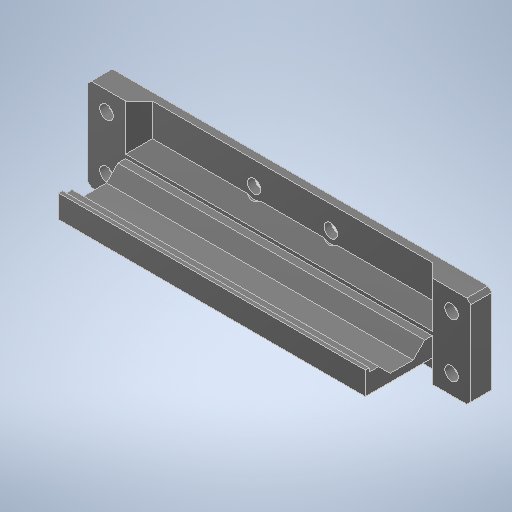
# Autodesk Inventor part: 3D_XT30-fix2
Saved by Autodesk Inventor 2025.3 (Build 293356030, 356C)
## iProperties
Created: 2025-09-07
Part Number: 3D_XT30-fix2
Material: 一般
Document SubType Name: Modeling
Designer: ibuki_ono
Density: 1 g/cm^3
Appearance: 滑らか - 黒
Author: ibuki_ono
## iProperties of the stored document 3D_XT30-fix2_3D プリント.ipt
Created: 2025-09-08
Part Number: 3D_XT30-fix2_3D プリント
Material: 一般
Document SubType Name: Modeling
Designer: ibuki_ono
Density: 1 g/cm^3
Appearance: 既定
Author: ibuki_ono
Autodesk Inventor part; units mm, degrees
(part 1 of 2)
ref_plane "YZ Plane" through (0, 0, 0) normal (1, 0, 0) x (0, 1, 0)
ref_plane "XZ Plane" through (0, 0, 0) normal (0, 1, 0) x (-1, 0, 0)
ref_plane "XY Plane" through (0, 0, 0) normal (0, 0, 1) x (1, 0, 0)
sketch "スケッチ1" plane through (0, 0, 0) normal (0, 0, 1) x (1, 0, 0)
  line L0 (-48, -5) -> (48, -5)
  line L1 (48, -5) -> (48, 5)
  line L2 (48, 5) -> (-48, 5)
  line L3 (-48, 5) -> (-48, -5)
  line L4 (-48, -5) -> (48, 5) construction
  line L5 (48, -5) -> (-48, 5) construction
  line L6 (-50, 7) -> (50, 7)
  line L7 (50, 7) -> (50, -7)
  line L8 (50, -7) -> (-50, -7)
  line L9 (-50, -7) -> (-50, 7)
  line L10 (-50, 5) -> (50, 5)
  line L11 (50, 5) -> (50, 17)
  line L12 (50, 17) -> (-50, 17)
  line L13 (-50, 17) -> (-50, 5)
  point P0 (0, 0)
  dimension "d0" = 96
  dimension "d1" = 10
  dimension "d2" = 2
  dimension "d3" = 12
  constraints: 28 end point, 6 parallel, 3 perpendicular, 2 horizontal, 2 midpoint, 1 collinear, 1 horizontal alignment, 1 point on line, 3 other
  measures "d0" distance of L2.end L1.end
  measures "d1" distance of L1.end L0.end
  measures "d2" distance between parallel lines of L2 L6
  measures "d3" distance of L12.end L10.start
extrude "押し出し1" add sketch "スケッチ1" along normal blind 2
sketch "スケッチ3" plane through (0, 0, 2) normal (0, 0, 1) x (1, 0, 0)
  line L0 (50, 17) -> (-50, 17) projected
  line L1 (50, -7) -> (50, 17) projected
  line L2 (-50, 17) -> (50, 17)
  line L3 (50, 17) -> (50, 5)
  line L4 (50, 5) -> (-50, 5)
  line L5 (-50, 5) -> (-50, 17)
  line L6 (-40, 5) -> (40, 5)
  line L7 (40, 5) -> (40, -1)
  line L8 (40, -1) -> (-40, -1)
  line L9 (-40, -1) -> (-40, 5)
  point P0 (0, 0)
  point P1 (0, 5)
  point P2 (40, 5)
  dimension "d6" = 12
  dimension "d7" = 80
  dimension "d8" = 6
  constraints: 16 end point, 4 parallel, 3 midpoint, 2 horizontal, 2 perpendicular, 1 point on line
  measures "d6" distance of L2.end L3.end
  measures "d7" distance of L7.end L8.end
  measures "d8" distance of L6.end L7.end
extrude "押し出し2" add sketch "スケッチ3" along normal blind 21 contours L7 L8 L9 L4
sketch "スケッチ5" plane through (-40, 5, 2) normal (0, 1, 0) x (1, 0, 0)
  line L0 (0, 0) -> (80, 0) projected
  line L1 (0, 0) -> (0, -21) projected
  line L2 (80, -21) -> (0, -21) projected
  line L3 (80, 0) -> (80, -21) projected
  line L4 (0, -20) -> (80, -20)
  line L5 (80, -20) -> (80, -3.5)
  line L6 (80, -3.5) -> (0, -3.5)
  line L7 (0, -3.5) -> (0, -20)
  point P0 (40, 2)
  point P1 (0, -3.5)
  dimension "d11" = 16.5
  dimension "d12" = 1
  constraints: 8 end point, 2 parallel, 2 point on line, 1 horizontal, 1 perpendicular
  measures "d11" distance between parallel lines of L6 L4
  measures "d12" distance between parallel lines of L2 L4
extrude "押し出し3" cut sketch "スケッチ5" against normal blind 1 contours L6 L3 L4 L1
sketch "スケッチ6" plane through (0, 0, 2) normal (0, 0, 1) x (1, 0, 0)
  line L0 (-50, 17) -> (-50, -7) projected
  line L1 (50, 17) -> (-50, 17) projected
  line L2 (-40, 5) -> (-40, -1) projected
  line L3 (-50, -7) -> (50, -7) projected
  line L4 (-50, -7) -> (-40, -7)
  line L5 (-40, -7) -> (-40, 17)
  line L6 (-40, 17) -> (-50, 17)
  line L7 (-50, 17) -> (-50, -7)
  point P0 (0, 0)
  point P1 (-40, -1)
  constraints: 8 end point, 2 parallel, 1 collinear, 1 horizontal, 1 perpendicular, 1 point on line
extrude "押し出し4" add sketch "スケッチ6" along normal blind 3.5
sketch "スケッチ7" plane through (-40, 4, 2) normal (0, 1, 0) x (1, 0, 0)
  line L0 (80, -3.5) -> (80, -20) projected
  line L1 (0, -3.5) -> (0, -21) projected
  line L2 (80, -17.5) -> (0, -17.5)
  line L3 (0, -17.5) -> (0, -5.5)
  line L4 (0, -5.5) -> (80, -5.5)
  line L5 (80, -5.5) -> (80, -17.5)
  line L6 (80, -20) -> (0, -20) projected
  point P0 (40, 2)
  point P1 (0, -17.5)
  dimension "d20" = 12
  dimension "d27" = 2.5
  constraints: 8 end point, 2 parallel, 2 point on line, 1 horizontal, 1 perpendicular
  measures "d20" distance between parallel lines of L2 L4
  measures "d27" distance between parallel lines of L6 L2
extrude "押し出し5" cut sketch "スケッチ7" against normal blind 3 contours L0 L2 L1 L4
chamfer "面取り2" distance 3 angle 45 2 edges at (0, 1, 7.5) (0, 1, 19.5)
sketch "スケッチ8" plane through (-40, 4, 5.5) normal (0, 0, 1) x (1, 0, 0)
  line L0 (0, 13) -> (-10, 13) projected
  line L1 (-10, -11) -> (0, -11) projected
  line L2 (-5, 13) -> (-5, -11) construction
  point P0 (40, -4)
  point P1 (-5, 8)
  point P2 (-5, -6)
  dimension "d28" = 5
  dimension "d29" = 5
  constraints: 2 end point, 2 midpoint, 2 point on line
  measures "d28" distance from line of L0 point (-5, 8)
  measures "d29" distance from line of L1 point (-5, -6)
hole "穴1" at (-45, 12, 5.5) at (-45, -2, 5.5) direction (0, 0, -1) diameter 3.5 end through all
sketch "スケッチ9" plane through (0, 0, 0) normal (0, 0, -1) x (-1, 0, 0)
  circle A0 centre (45, -2) radius 1.75 projected
  line L0 (45, -5.1754) -> (42.25, -3.5877)
  line L1 (42.25, -3.5877) -> (42.25, -0.4123)
  line L2 (42.25, -0.4123) -> (45, 1.1754)
  line L3 (45, 1.1754) -> (47.75, -0.4123)
  line L4 (47.75, -0.4123) -> (47.75, -3.5877)
  line L5 (47.75, -3.5877) -> (45, -5.1754)
  point P0 (0, 0)
  dimension "d37" = 5.5
  constraints: 12 end point, 1 coincident, 1 vertical alignment, 13 other
  measures "d37" distance between parallel lines of L1 L4
extrude "押し出し6" cut sketch "スケッチ9" against normal blind 3
sketch "スケッチ10" plane through (0, 0, 3) normal (0, 0, -1) x (-1, 0, 0)
  line L0 (47.75, -0.4123) -> (47.75, -3.5877) projected
  line L1 (45, 1.1754) -> (47.75, -0.4123) projected
  line L2 (42.25, -0.4123) -> (45, 1.1754) projected
  line L3 (42.25, -3.5877) -> (42.25, -0.4123) projected
  line L4 (45, -5.1754) -> (42.25, -3.5877) projected
  line L5 (47.75, -3.5877) -> (45, -5.1754) projected
  circle A0 centre (45, -2) radius 1.75 projected
  line L6 (46.75, -4.1651) -> (46.75, 0.1651)
  line L7 (46, 0.5981) -> (42.25, -1.567)
  line L8 (42.25, -2.433) -> (46, -4.5981)
  line L9 (45, -5.1754) -> (42.25, -3.5877) projected
  line L10 (47.75, -0.4123) -> (47.75, -3.5877) projected
  line L11 (42.25, -0.4123) -> (45, 1.1754) projected
  circle A1 centre (45, -2) radius 1.75 projected
  point P0 (0, 0)
  point P1 (44.125, -3.5155)
  point P2 (44.125, -0.4845)
  point P3 (46.75, -2)
  constraints: 6 end point, 6 point on line, 4 parallel, 3 tangent, 1 vertical
extrude "押し出し7" cut sketch "スケッチ10" against normal blind 0.2 contours L6 A0 L7 L1 | L5 L8 A0 L6 | A0 L8 L3 L7
pattern_linear "矩形状パターン1" count 2 spacing 14 along (0, 1, 0) of "押し出し6", "押し出し7"
mirror "ミラー1" about plane through (0, 0, 0) normal (1, 0, 0) of "押し出し4", "穴1", "押し出し6", "押し出し7", "矩形状パターン1"
chamfer "面取り3" distance 1 angle 45 4 edges at (-50, -7, 2.75) (-50, 17, 2.75) (50, -7, 2.75) (50, 17, 2.75)
chamfer "面取り4" distance 3.5 angle 45 8 edges at (-40, -4, 2) (-40, -1, 3.75) (0, -1, 2) (40, -4, 2) (40, -1, 3.75) (40, 11, 2) (0, 5, 2) (-40, 11, 2)
sketch "スケッチ11" plane through (0, 0, 2) normal (0, 0, 1) x (1, 0, 0)
  line L0 (-10, 11) -> (10, 11) construction
  line L1 (-10, 11) -> (10, 11) construction
  line L2 (36.5, 17) -> (-36.5, 17) construction
  point P0 (0, 0)
  point P1 (0, 11)
  point P2 (0, 17)
  dimension "d51" = 20
  dimension "d52" = 0
  dimension "d53" = 6
  constraints: 4 end point, 2 coincident, 2 horizontal, 2 midpoint, 1 collinear, 1 vertical alignment
  measures "d51" distance of L0.start L0.end
  measures "d52" distance between parallel lines of L0 L1
  measures "d53" distance between parallel lines of L2 L0
hole "穴2" at (-10, 11, 2) at (10, 11, 2) direction (0, 0, -1) diameter 3.5 end through all
sketch "スケッチ12" plane through (0, 0, 2) normal (0, 0, 1) x (1, 0, 0)
  circle A0 centre (10, 11) radius 1.75 projected
  circle A1 centre (-10, 11) radius 1.75 projected
  circle A2 centre (10, 11) radius 3
  circle A3 centre (-10, 11) radius 3
  point P0 (0, 0)
  dimension "d61" = 6
  dimension "d62" = 6
  constraints: 2 centre point, 2 coincident
  measures "d61" diameter of A2
  measures "d62" diameter of A3
extrude "押し出し8" cut sketch "スケッチ12" along normal blind 1
sketch "スケッチ13" plane through (-40, -1, 23) normal (0, -1, 0) x (1, 0, 0)
  line L0 (2.7364, -3.5747) -> (85.0579, -3.5747) construction
  line L1 (85.0579, -3.5747) -> (85.0579, -25.4709) construction
  line L2 (85.0579, -25.4709) -> (2.7364, -25.4709) construction
  line L3 (2.7364, -25.4709) -> (2.7364, -3.5747) construction
  spline S0 degree 2 poles (6.5541, -4.6526) (6.6178, -4.3658) (6.6603, -4.0791) knots 0 0 0 1 1 1
  spline S1 degree 2 poles (6.6603, -4.0791) (6.7027, -3.8455) (6.7027, -3.5747) knots 0 0 0 1 1 1
  spline S2 degree 2 poles (6.7027, -3.5747) (7.239, -3.7128) (7.3824, -3.7765) knots 0 0 0 1 1 1
  spline S3 degree 2 poles (7.3824, -3.7765) (7.478, -3.8243) (7.478, -3.8827) knots 0 0 0 1 1 1
  spline S4 degree 2 poles (7.478, -3.8827) (7.478, -3.9995) (7.1753, -4.0526) knots 0 0 0 1 1 1
  spline S5 degree 2 poles (7.1753, -4.0526) (6.9788, -4.4136) (6.793, -4.6526) knots 0 0 0 1 1 1
  line L4 (6.793, -4.6526) -> (7.701, -4.6526)
  spline S6 degree 2 poles (7.701, -4.6526) (7.9399, -4.3977) (7.993, -4.3977) knots 0 0 0 1 1 1
  spline S7 degree 2 poles (7.993, -4.3977) (8.0514, -4.3977) (8.3063, -4.6207) knots 0 0 0 1 1 1
  spline S8 degree 2 poles (8.3063, -4.6207) (8.439, -4.7428) (8.439, -4.8172) knots 0 0 0 1 1 1
  spline S9 degree 2 poles (8.439, -4.8172) (8.439, -4.8809) (8.2319, -5.0189) knots 0 0 0 1 1 1
  line L5 (8.2319, -5.0189) -> (8.2319, -5.7198)
  line L6 (8.2319, -5.7198) -> (8.2532, -7.4349)
  spline S10 degree 2 poles (8.2532, -7.4349) (8.2532, -7.6366) (7.9665, -7.6366) knots 0 0 0 1 1 1
  spline S11 degree 2 poles (7.9665, -7.6366) (7.7488, -7.6366) (7.7488, -7.4667) knots 0 0 0 1 1 1
  line L7 (7.7488, -7.4667) -> (7.7488, -7.265)
  line L8 (7.7488, -7.265) -> (6.0921, -7.265)
  line L9 (6.0921, -7.265) -> (6.0921, -7.4827)
  spline S12 degree 2 poles (6.0921, -7.4827) (6.0921, -7.6951) (5.7895, -7.6951) knots 0 0 0 1 1 1
  spline S13 degree 2 poles (5.7895, -7.6951) (5.5877, -7.6951) (5.5877, -7.5251) knots 0 0 0 1 1 1
  line L10 (5.5877, -7.5251) -> (5.6195, -5.8048)
  spline S14 degree 2 poles (5.6195, -5.8048) (5.6195, -4.8543) (5.5771, -4.3658) knots 0 0 0 1 1 1
  spline S15 degree 2 poles (5.5771, -4.3658) (5.8319, -4.4667) (6.1611, -4.6526) knots 0 0 0 1 1 1
  line L11 (6.1611, -4.6526) -> (6.5541, -4.6526)
  line L12 (6.6125, -8.4172) -> (6.6125, -8.3269)
  spline S16 degree 2 poles (6.6125, -8.3269) (6.6125, -7.8331) (6.57, -7.5145) knots 0 0 0 1 1 1
  spline S17 degree 2 poles (6.57, -7.5145) (7.4036, -7.5835) (7.4036, -7.7269) knots 0 0 0 1 1 1
  spline S18 degree 2 poles (7.4036, -7.7269) (7.4036, -7.8278) (7.1116, -7.9287) knots 0 0 0 1 1 1
  line L13 (7.1116, -7.9287) -> (7.1116, -8.4172)
  line L14 (7.1116, -8.4172) -> (9.5116, -8.4172)
  spline S19 degree 2 poles (9.5116, -8.4172) (9.8992, -7.9924) (9.9629, -7.9924) knots 0 0 0 1 1 1
  spline S20 degree 2 poles (9.9629, -7.9924) (10.0266, -7.9924) (10.4302, -8.3216) knots 0 0 0 1 1 1
  spline S21 degree 2 poles (10.4302, -8.3216) (10.6319, -8.4915) (10.6319, -8.5552) knots 0 0 0 1 1 1
  spline S22 degree 2 poles (10.6319, -8.5552) (10.6319, -8.6296) (10.5204, -8.6296) knots 0 0 0 1 1 1
  line L15 (10.5204, -8.6296) -> (7.2231, -8.6296)
  spline S23 degree 2 poles (7.2231, -8.6296) (7.8603, -9.2561) (8.7629, -9.6862) knots 0 0 0 1 1 1
  spline S24 degree 2 poles (8.7629, -9.6862) (9.6018, -10.0951) (10.8284, -10.249) knots 0 0 0 1 1 1
  spline S25 degree 2 poles (10.8284, -10.249) (10.8603, -10.249) (10.8603, -10.2809) knots 0 0 0 1 1 1
  spline S26 degree 2 poles (10.8603, -10.2809) (10.8603, -10.3234) (10.8231, -10.3287) knots 0 0 0 1 1 1
  spline S27 degree 2 poles (10.8231, -10.3287) (10.6319, -10.3818) (10.5629, -10.4614) knots 0 0 0 1 1 1
  spline S28 degree 2 poles (10.5629, -10.4614) (10.4886, -10.5358) (10.4089, -10.7428) knots 0 0 0 1 1 1
  spline S29 degree 2 poles (10.4089, -10.7428) (10.3665, -10.8384) (10.2656, -10.8384) knots 0 0 0 1 1 1
  spline S30 degree 2 poles (10.2656, -10.8384) (10.17, -10.8384) (9.9735, -10.7694) knots 0 0 0 1 1 1
  spline S31 degree 2 poles (9.9735, -10.7694) (9.1877, -10.5039) (8.5877, -10.1004) knots 0 0 0 1 1 1
  spline S32 degree 2 poles (8.5877, -10.1004) (7.8496, -9.6225) (7.0797, -8.7145) knots 0 0 0 1 1 1
  line L16 (7.0797, -8.7145) -> (7.1594, -11.0136)
  spline S33 degree 2 poles (7.1594, -11.0136) (7.1594, -11.2579) (6.8142, -11.2579) knots 0 0 0 1 1 1
  spline S34 degree 2 poles (6.8142, -11.2579) (6.5859, -11.2579) (6.5859, -11.0561) knots 0 0 0 1 1 1
  spline S35 degree 2 poles (6.5859, -11.0561) (6.5859, -10.8703) (6.6231, -9.8561) knots 0 0 0 1 1 1
  line L17 (6.6231, -9.8561) -> (6.6603, -8.9269)
  spline S36 degree 2 poles (6.6603, -8.9269) (5.2426, -10.3393) (3.1771, -10.9287) knots 0 0 0 1 1 1
  spline S37 degree 2 poles (3.1771, -10.9287) (3.1718, -10.9287) (3.1665, -10.9287) knots 0 0 0 1 1 1
  spline S38 degree 2 poles (3.1665, -10.9287) (3.1134, -10.9287) (3.1134, -10.849) knots 0 0 0 1 1 1
  spline S39 degree 2 poles (3.1134, -10.849) (3.1134, -10.8172) (3.1346, -10.8066) knots 0 0 0 1 1 1
  spline S40 degree 2 poles (3.1346, -10.8066) (5.1151, -9.9676) (6.2355, -8.6296) knots 0 0 0 1 1 1
  line L18 (6.2355, -8.6296) -> (3.9682, -8.6296)
  spline S41 degree 2 poles (3.9682, -8.6296) (3.7187, -8.6296) (3.3629, -8.6774) knots 0 0 0 1 1 1
  line L19 (3.3629, -8.6774) -> (3.2833, -8.3588)
  spline S42 degree 2 poles (3.2833, -8.3588) (3.5806, -8.4172) (3.9629, -8.4172) knots 0 0 0 1 1 1
  line L20 (3.9629, -8.4172) -> (6.6125, -8.4172)
  line L21 (7.7488, -7.0526) -> (7.7488, -6.0384)
  line L22 (7.7488, -6.0384) -> (6.0921, -6.0384)
  line L23 (6.0921, -6.0384) -> (6.0921, -7.0526)
  line L24 (6.0921, -7.0526) -> (7.7488, -7.0526)
  line L25 (7.7488, -5.826) -> (7.7488, -4.865)
  line L26 (7.7488, -4.865) -> (6.0921, -4.865)
  line L27 (6.0921, -4.865) -> (6.0921, -5.826)
  line L28 (6.0921, -5.826) -> (7.7488, -5.826)
  spline S43 degree 2 poles (8.5505, -6.1818) (8.5293, -6.1712) (8.5293, -6.1446) knots 0 0 0 1 1 1
  spline S44 degree 2 poles (8.5293, -6.1446) (8.5293, -6.0809) (8.5877, -6.0862) knots 0 0 0 1 1 1
  spline S45 degree 2 poles (8.5877, -6.0862) (9.5594, -6.3092) (10.0532, -6.665) knots 0 0 0 1 1 1
  spline S46 degree 2 poles (10.0532, -6.665) (10.4567, -6.957) (10.4567, -7.2703) knots 0 0 0 1 1 1
  spline S47 degree 2 poles (10.4567, -7.2703) (10.4567, -7.3977) (10.3824, -7.4827) knots 0 0 0 1 1 1
  spline S48 degree 2 poles (10.3824, -7.4827) (10.3134, -7.5623) (10.2072, -7.5623) knots 0 0 0 1 1 1
  spline S49 degree 2 poles (10.2072, -7.5623) (10.0479, -7.5623) (9.8514, -7.2968) knots 0 0 0 1 1 1
  spline S50 degree 2 poles (9.8514, -7.2968) (9.3842, -6.6119) (8.5505, -6.1818) knots 0 0 0 1 1 1
  spline S51 degree 2 poles (5.3647, -6.2083) (5.37, -6.1977) (5.3806, -6.1977) knots 0 0 0 1 1 1
  spline S52 degree 2 poles (5.3806, -6.1977) (5.4284, -6.1977) (5.4284, -6.272) knots 0 0 0 1 1 1
  spline S53 degree 2 poles (5.4284, -6.272) (5.4284, -6.2933) (5.4125, -6.3039) knots 0 0 0 1 1 1
  spline S54 degree 2 poles (5.4125, -6.3039) (4.8125, -6.9145) (3.8089, -7.4933) knots 0 0 0 1 1 1
  spline S55 degree 2 poles (3.8089, -7.4933) (3.7983, -7.8066) (3.6762, -7.8066) knots 0 0 0 1 1 1
  spline S56 degree 2 poles (3.6762, -7.8066) (3.5859, -7.8066) (3.278, -7.0791) knots 0 0 0 1 1 1
  spline S57 degree 2 poles (3.278, -7.0791) (3.501, -7.0366) (3.708, -6.9676) knots 0 0 0 1 1 1
  spline S58 degree 2 poles (3.708, -6.9676) (4.4939, -6.6862) (5.3647, -6.2083) knots 0 0 0 1 1 1
  spline S59 degree 2 poles (8.6089, -5.7942) (8.5983, -5.7942) (8.593, -5.7942) knots 0 0 0 1 1 1
  spline S60 degree 2 poles (8.593, -5.7942) (8.5293, -5.7942) (8.5293, -5.7145) knots 0 0 0 1 1 1
  spline S61 degree 2 poles (8.5293, -5.7145) (8.5293, -5.6933) (8.5399, -5.6774) knots 0 0 0 1 1 1
  spline S62 degree 2 poles (8.5399, -5.6774) (9.1187, -5.1729) (9.5381, -4.6207) knots 0 0 0 1 1 1
  spline S63 degree 2 poles (9.5381, -4.6207) (9.7399, -4.3499) (9.8992, -4.0579) knots 0 0 0 1 1 1
  spline S64 degree 2 poles (9.8992, -4.0579) (10.5364, -4.472) (10.5364, -4.5889) knots 0 0 0 1 1 1
  spline S65 degree 2 poles (10.5364, -4.5889) (10.5364, -4.6791) (10.3665, -4.6791) knots 0 0 0 1 1 1
  spline S66 degree 2 poles (10.3665, -4.6791) (10.2921, -4.6791) (10.1912, -4.6632) knots 0 0 0 1 1 1
  spline S67 degree 2 poles (10.1912, -4.6632) (9.5116, -5.2951) (8.6089, -5.7942) knots 0 0 0 1 1 1
  spline S68 degree 2 poles (3.4638, -4.3074) (3.4479, -4.2968) (3.4479, -4.2756) knots 0 0 0 1 1 1
  spline S69 degree 2 poles (3.4479, -4.2756) (3.4479, -4.2066) (3.5116, -4.2066) knots 0 0 0 1 1 1
  spline S70 degree 2 poles (3.5116, -4.2066) (3.5222, -4.2066) (3.5222, -4.2119) knots 0 0 0 1 1 1
  spline S71 degree 2 poles (3.5222, -4.2119) (4.2815, -4.4508) (4.6744, -4.78) knots 0 0 0 1 1 1
  spline S72 degree 2 poles (4.6744, -4.78) (5.0142, -5.0667) (5.0142, -5.3535) knots 0 0 0 1 1 1
  spline S73 degree 2 poles (5.0142, -5.3535) (5.0142, -5.6986) (4.7222, -5.6986) knots 0 0 0 1 1 1
  spline S74 degree 2 poles (4.7222, -5.6986) (4.5735, -5.6986) (4.4302, -5.4012) knots 0 0 0 1 1 1
  spline S75 degree 2 poles (4.4302, -5.4012) (4.1063, -4.78) (3.4638, -4.3074) knots 0 0 0 1 1 1
  spline S76 degree 2 poles (14.9753, -10.6366) (13.6903, -10.6366) (13.6903, -9.3198) knots 0 0 0 1 1 1
  spline S77 degree 2 poles (13.6903, -9.3198) (13.6903, -8.7198) (13.7594, -7.2172) knots 0 0 0 1 1 1
  spline S78 degree 2 poles (13.7594, -7.2172) (13.7965, -6.5057) (13.8284, -5.1305) knots 0 0 0 1 1 1
  spline S79 degree 2 poles (13.8284, -5.1305) (13.839, -4.6154) (13.4514, -4.5039) knots 0 0 0 1 1 1
  spline S80 degree 2 poles (13.4514, -4.5039) (13.3293, -4.472) (13.3293, -4.4136) knots 0 0 0 1 1 1
  spline S81 degree 2 poles (13.3293, -4.4136) (13.3293, -4.3605) (13.4142, -4.3074) knots 0 0 0 1 1 1
  spline S82 degree 2 poles (13.4142, -4.3074) (13.4833, -4.2756) (13.616, -4.2756) knots 0 0 0 1 1 1
  spline S83 degree 2 poles (13.616, -4.2756) (13.8549, -4.2756) (14.2054, -4.5358) knots 0 0 0 1 1 1
  spline S84 degree 2 poles (14.2054, -4.5358) (14.5558, -4.7959) (14.5558, -5.0189) knots 0 0 0 1 1 1
  spline S85 degree 2 poles (14.5558, -5.0189) (14.5558, -5.1464) (14.4337, -5.2632) knots 0 0 0 1 1 1
  spline S86 degree 2 poles (14.4337, -5.2632) (14.3434, -5.3588) (14.3275, -5.5765) knots 0 0 0 1 1 1
  spline S87 degree 2 poles (14.3275, -5.5765) (14.2426, -6.2455) (14.1842, -7.2437) knots 0 0 0 1 1 1
  spline S88 degree 2 poles (14.1842, -7.2437) (14.1045, -8.5393) (14.1045, -9.2189) knots 0 0 0 1 1 1
  spline S89 degree 2 poles (14.1045, -9.2189) (14.1045, -9.803) (14.3381, -9.9995) knots 0 0 0 1 1 1
  spline S90 degree 2 poles (14.3381, -9.9995) (14.5293, -10.18) (15.0072, -10.18) knots 0 0 0 1 1 1
  spline S91 degree 2 poles (15.0072, -10.18) (15.862, -10.18) (16.7912, -9.7021) knots 0 0 0 1 1 1
  spline S92 degree 2 poles (16.7912, -9.7021) (17.5346, -9.3198) (18.1824, -8.7092) knots 0 0 0 1 1 1
  spline S93 degree 2 poles (18.1824, -8.7092) (18.2355, -8.6508) (18.3098, -8.6508) knots 0 0 0 1 1 1
  spline S94 degree 2 poles (18.3098, -8.6508) (18.3895, -8.6508) (18.3895, -8.7411) knots 0 0 0 1 1 1
  spline S95 degree 2 poles (18.3895, -8.7411) (18.3895, -8.7889) (18.3311, -8.8632) knots 0 0 0 1 1 1
  spline S96 degree 2 poles (18.3311, -8.8632) (17.6886, -9.6968) (16.7116, -10.1853) knots 0 0 0 1 1 1
  spline S97 degree 2 poles (16.7116, -10.1853) (15.8302, -10.6366) (14.9753, -10.6366) knots 0 0 0 1 1 1
  spline S98 degree 2 poles (24.0072, -3.9782) (24.2939, -3.9782) (24.6337, -4.3021) knots 0 0 0 1 1 1
  spline S99 degree 2 poles (24.6337, -4.3021) (24.947, -4.5995) (24.947, -4.78) knots 0 0 0 1 1 1
  spline S100 degree 2 poles (24.947, -4.78) (24.947, -4.9552) (24.7505, -5.0243) knots 0 0 0 1 1 1
  spline S101 degree 2 poles (24.7505, -5.0243) (24.6443, -5.072) (24.4903, -5.2048) knots 0 0 0 1 1 1
  spline S102 degree 2 poles (24.4903, -5.2048) (23.4921, -6.065) (22.5576, -7.1694) knots 0 0 0 1 1 1
  spline S103 degree 2 poles (22.5576, -7.1694) (22.4461, -7.3074) (22.4461, -7.403) knots 0 0 0 1 1 1
  spline S104 degree 2 poles (22.4461, -7.403) (22.4461, -7.5251) (22.6054, -7.6632) knots 0 0 0 1 1 1
  spline S105 degree 2 poles (22.6054, -7.6632) (24.0762, -8.8897) (24.8195, -9.8508) knots 0 0 0 1 1 1
  spline S106 degree 2 poles (24.8195, -9.8508) (25.2231, -10.3871) (25.2231, -10.626) knots 0 0 0 1 1 1
  spline S107 degree 2 poles (25.2231, -10.626) (25.2231, -10.7853) (25.1222, -10.8756) knots 0 0 0 1 1 1
  spline S108 degree 2 poles (25.1222, -10.8756) (25.0372, -10.9499) (24.9257, -10.9499) knots 0 0 0 1 1 1
  spline S109 degree 2 poles (24.9257, -10.9499) (24.7611, -10.9499) (24.6125, -10.6526) knots 0 0 0 1 1 1
  spline S110 degree 2 poles (24.6125, -10.6526) (24.0178, -9.4738) (22.3558, -7.9605) knots 0 0 0 1 1 1
  spline S111 degree 2 poles (22.3558, -7.9605) (22.0638, -7.7004) (22.0638, -7.4614) knots 0 0 0 1 1 1
  spline S112 degree 2 poles (22.0638, -7.4614) (22.0638, -7.2384) (22.2656, -6.9835) knots 0 0 0 1 1 1
  spline S113 degree 2 poles (22.2656, -6.9835) (23.1735, -5.8897) (24.0178, -4.9605) knots 0 0 0 1 1 1
  spline S114 degree 2 poles (24.0178, -4.9605) (24.2355, -4.711) (24.2355, -4.5782) knots 0 0 0 1 1 1
  spline S115 degree 2 poles (24.2355, -4.5782) (24.2355, -4.3871) (23.9222, -4.1641) knots 0 0 0 1 1 1
  spline S116 degree 2 poles (23.9222, -4.1641) (23.8372, -4.1004) (23.8372, -4.0685) knots 0 0 0 1 1 1
  spline S117 degree 2 poles (23.8372, -4.0685) (23.8372, -3.9782) (24.0072, -3.9782) knots 0 0 0 1 1 1
  spline S118 degree 2 poles (34.016, -6.665) (33.724, -6.5641) (33.2833, -6.5641) knots 0 0 0 1 1 1
  spline S119 degree 2 poles (33.2833, -6.5641) (33.0549, -6.5641) (32.8372, -6.6012) knots 0 0 0 1 1 1
  spline S120 degree 2 poles (32.8372, -6.6012) (32.8213, -6.6012) (32.816, -6.6012) knots 0 0 0 1 1 1
  spline S121 degree 2 poles (32.816, -6.6012) (32.7098, -6.6012) (32.7098, -6.5322) knots 0 0 0 1 1 1
  spline S122 degree 2 poles (32.7098, -6.5322) (32.7098, -6.442) (32.8266, -6.4048) knots 0 0 0 1 1 1
  spline S123 degree 2 poles (32.8266, -6.4048) (33.1558, -6.3145) (33.5434, -6.3145) knots 0 0 0 1 1 1
  spline S124 degree 2 poles (33.5434, -6.3145) (33.9523, -6.3145) (34.3718, -6.426) knots 0 0 0 1 1 1
  spline S125 degree 2 poles (34.3718, -6.426) (34.7594, -6.5375) (35.0036, -6.7021) knots 0 0 0 1 1 1
  spline S126 degree 2 poles (35.0036, -6.7021) (35.3594, -6.9411) (35.3594, -7.1853) knots 0 0 0 1 1 1
  spline S127 degree 2 poles (35.3594, -7.1853) (35.3594, -7.2703) (35.301, -7.334) knots 0 0 0 1 1 1
  spline S128 degree 2 poles (35.301, -7.334) (35.2372, -7.3924) (35.1523, -7.3924) knots 0 0 0 1 1 1
  spline S129 degree 2 poles (35.1523, -7.3924) (35.0036, -7.3924) (34.8709, -7.2597) knots 0 0 0 1 1 1
  spline S130 degree 2 poles (34.8709, -7.2597) (34.5417, -6.9305) (34.1753, -6.9305) knots 0 0 0 1 1 1
  spline S131 degree 2 poles (34.1753, -6.9305) (33.8195, -6.9305) (33.5806, -7.1694) knots 0 0 0 1 1 1
  spline S132 degree 2 poles (33.5806, -7.1694) (33.3682, -7.3871) (33.3682, -7.6897) knots 0 0 0 1 1 1
  spline S133 degree 2 poles (33.3682, -7.6897) (33.3682, -8.0296) (33.4638, -8.5446) knots 0 0 0 1 1 1
  spline S134 degree 2 poles (33.4638, -8.5446) (33.4903, -8.6933) (33.5594, -9.0012) knots 0 0 0 1 1 1
  spline S135 degree 2 poles (33.5594, -9.0012) (33.6072, -9.2296) (33.6284, -9.3517) knots 0 0 0 1 1 1
  spline S136 degree 2 poles (33.6284, -9.3517) (34.7859, -9.7181) (35.1895, -10.0844) knots 0 0 0 1 1 1
  spline S137 degree 2 poles (35.1895, -10.0844) (35.3328, -10.2066) (35.3328, -10.3818) knots 0 0 0 1 1 1
  spline S138 degree 2 poles (35.3328, -10.3818) (35.3328, -10.626) (35.0833, -10.626) knots 0 0 0 1 1 1
  spline S139 degree 2 poles (35.0833, -10.626) (34.9665, -10.6154) (34.8603, -10.5305) knots 0 0 0 1 1 1
  spline S140 degree 2 poles (34.8603, -10.5305) (34.1806, -9.9995) (33.6603, -9.7977) knots 0 0 0 1 1 1
  spline S141 degree 2 poles (33.6603, -9.7977) (33.6337, -10.2968) (33.3842, -10.5623) knots 0 0 0 1 1 1
  spline S142 degree 2 poles (33.3842, -10.5623) (33.0762, -10.8862) (32.37, -10.8862) knots 0 0 0 1 1 1
  spline S143 degree 2 poles (32.37, -10.8862) (31.7965, -10.8862) (31.4726, -10.6154) knots 0 0 0 1 1 1
  spline S144 degree 2 poles (31.4726, -10.6154) (31.2125, -10.3977) (31.2125, -10.0844) knots 0 0 0 1 1 1
  spline S145 degree 2 poles (31.2125, -10.0844) (31.2125, -9.6597) (31.6319, -9.4048) knots 0 0 0 1 1 1
  spline S146 degree 2 poles (31.6319, -9.4048) (31.9718, -9.1977) (32.4443, -9.1977) knots 0 0 0 1 1 1
  spline S147 degree 2 poles (32.4443, -9.1977) (32.9222, -9.1977) (33.1824, -9.2561) knots 0 0 0 1 1 1
  spline S148 degree 2 poles (33.1824, -9.2561) (33.0443, -8.0455) (33.0443, -7.9021) knots 0 0 0 1 1 1
  spline S149 degree 2 poles (33.0443, -7.9021) (33.0443, -7.3924) (33.3151, -7.111) knots 0 0 0 1 1 1
  spline S150 degree 2 poles (33.3151, -7.111) (33.5381, -6.872) (34.0107, -6.7393) knots 0 0 0 1 1 1
  spline S151 degree 2 poles (34.0107, -6.7393) (34.0532, -6.7234) (34.0532, -6.6968) knots 0 0 0 1 1 1
  spline S152 degree 2 poles (34.0532, -6.6968) (34.0532, -6.6809) (34.016, -6.665) knots 0 0 0 1 1 1
  spline S153 degree 2 poles (31.0319, -6.065) (30.5434, -6.1499) (30.0868, -6.1499) knots 0 0 0 1 1 1
  spline S154 degree 2 poles (30.0868, -6.1499) (29.8107, -6.1499) (29.5611, -6.0172) knots 0 0 0 1 1 1
  spline S155 degree 2 poles (29.5611, -6.0172) (29.3381, -5.9004) (29.2372, -5.7092) knots 0 0 0 1 1 1
  spline S156 degree 2 poles (29.2372, -5.7092) (29.2001, -5.6402) (29.2001, -5.603) knots 0 0 0 1 1 1
  spline S157 degree 2 poles (29.2001, -5.603) (29.2001, -5.5393) (29.2691, -5.5393) knots 0 0 0 1 1 1
  spline S158 degree 2 poles (29.2691, -5.5393) (29.3169, -5.5393) (29.3965, -5.5871) knots 0 0 0 1 1 1
  spline S159 degree 2 poles (29.3965, -5.5871) (29.6726, -5.7889) (30.0709, -5.7889) knots 0 0 0 1 1 1
  spline S160 degree 2 poles (30.0709, -5.7889) (30.4903, -5.7995) (31.2019, -5.6508) knots 0 0 0 1 1 1
  spline S161 degree 2 poles (31.2019, -5.6508) (31.3505, -5.2897) (31.4992, -4.8225) knots 0 0 0 1 1 1
  spline S162 degree 2 poles (31.4992, -4.8225) (31.5417, -4.6632) (31.5417, -4.5251) knots 0 0 0 1 1 1
  spline S163 degree 2 poles (31.5417, -4.5251) (31.5417, -4.4083) (31.3877, -4.3128) knots 0 0 0 1 1 1
  spline S164 degree 2 poles (31.3877, -4.3128) (31.2231, -4.2119) (31.0638, -4.1853) knots 0 0 0 1 1 1
  spline S165 degree 2 poles (31.0638, -4.1853) (31.0001, -4.1694) (31.0001, -4.1375) knots 0 0 0 1 1 1
  spline S166 degree 2 poles (31.0001, -4.1375) (31.0001, -3.9835) (31.2868, -3.9835) knots 0 0 0 1 1 1
  spline S167 degree 2 poles (31.2868, -3.9835) (31.5417, -3.9835) (31.9452, -4.18) knots 0 0 0 1 1 1
  spline S168 degree 2 poles (31.9452, -4.18) (32.216, -4.3074) (32.216, -4.4402) knots 0 0 0 1 1 1
  spline S169 degree 2 poles (32.216, -4.4402) (32.216, -4.5676) (32.1151, -4.6366) knots 0 0 0 1 1 1
  spline S170 degree 2 poles (32.1151, -4.6366) (32.0249, -4.6951) (31.8974, -4.9818) knots 0 0 0 1 1 1
  spline S171 degree 2 poles (31.8974, -4.9818) (31.8868, -5.003) (31.7806, -5.2526) knots 0 0 0 1 1 1
  spline S172 degree 2 poles (31.7806, -5.2526) (31.7116, -5.4172) (31.6532, -5.5499) knots 0 0 0 1 1 1
  spline S173 degree 2 poles (31.6532, -5.5499) (31.9877, -5.4543) (32.37, -5.2791) knots 0 0 0 1 1 1
  spline S174 degree 2 poles (32.37, -5.2791) (32.6567, -5.1411) (32.8001, -5.1411) knots 0 0 0 1 1 1
  spline S175 degree 2 poles (32.8001, -5.1411) (32.9063, -5.1411) (32.9859, -5.2154) knots 0 0 0 1 1 1
  spline S176 degree 2 poles (32.9859, -5.2154) (33.0709, -5.2738) (33.0709, -5.3694) knots 0 0 0 1 1 1
  spline S177 degree 2 poles (33.0709, -5.3694) (33.0709, -5.5446) (32.7895, -5.6402) knots 0 0 0 1 1 1
  spline S178 degree 2 poles (32.7895, -5.6402) (32.1576, -5.8473) (31.4673, -5.9959) knots 0 0 0 1 1 1
  spline S179 degree 2 poles (31.4673, -5.9959) (30.4957, -8.226) (29.8691, -9.4685) knots 0 0 0 1 1 1
  spline S180 degree 2 poles (29.8691, -9.4685) (29.7895, -9.6331) (29.5877, -9.6331) knots 0 0 0 1 1 1
  spline S181 degree 2 poles (29.5877, -9.6331) (29.4921, -9.6331) (29.4178, -9.5481) knots 0 0 0 1 1 1
  spline S182 degree 2 poles (29.4178, -9.5481) (29.3647, -9.4791) (29.3647, -9.3835) knots 0 0 0 1 1 1
  spline S183 degree 2 poles (29.3647, -9.3835) (29.3647, -9.272) (29.4178, -9.1818) knots 0 0 0 1 1 1
  spline S184 degree 2 poles (29.4178, -9.1818) (30.3098, -7.7269) (31.0319, -6.065) knots 0 0 0 1 1 1
  spline S185 degree 2 poles (33.2142, -9.6437) (32.8638, -9.5216) (32.4496, -9.5216) knots 0 0 0 1 1 1
  spline S186 degree 2 poles (32.4496, -9.5216) (31.9983, -9.5216) (31.7222, -9.6756) knots 0 0 0 1 1 1
  spline S187 degree 2 poles (31.7222, -9.6756) (31.4726, -9.8189) (31.4726, -10.0526) knots 0 0 0 1 1 1
  spline S188 degree 2 poles (31.4726, -10.0526) (31.4726, -10.265) (31.701, -10.3924) knots 0 0 0 1 1 1
  spline S189 degree 2 poles (31.701, -10.3924) (31.9134, -10.5092) (32.285, -10.5092) knots 0 0 0 1 1 1
  spline S190 degree 2 poles (32.285, -10.5092) (32.7629, -10.5092) (32.9859, -10.2968) knots 0 0 0 1 1 1
  spline S191 degree 2 poles (32.9859, -10.2968) (33.1983, -10.1004) (33.2142, -9.6437) knots 0 0 0 1 1 1
  spline S192 degree 2 poles (41.5824, -6.7552) (42.3576, -6.7552) (42.8408, -7.2066) knots 0 0 0 1 1 1
  spline S193 degree 2 poles (42.8408, -7.2066) (43.3187, -7.6526) (43.3187, -8.2897) knots 0 0 0 1 1 1
  spline S194 degree 2 poles (43.3187, -8.2897) (43.3187, -9.2349) (42.2673, -9.8296) knots 0 0 0 1 1 1
  spline S195 degree 2 poles (42.2673, -9.8296) (41.4178, -10.2968) (40.2178, -10.3818) knots 0 0 0 1 1 1
  spline S196 degree 2 poles (40.2178, -10.3818) (40.1381, -10.3924) (39.9948, -10.3924) knots 0 0 0 1 1 1
  spline S197 degree 2 poles (39.9948, -10.3924) (39.8408, -10.3924) (39.8408, -10.2703) knots 0 0 0 1 1 1
  spline S198 degree 2 poles (39.8408, -10.2703) (39.8408, -10.18) (39.9682, -10.1641) knots 0 0 0 1 1 1
  spline S199 degree 2 poles (39.9682, -10.1641) (41.1735, -10.0048) (41.9275, -9.5481) knots 0 0 0 1 1 1
  spline S200 degree 2 poles (41.9275, -9.5481) (42.7983, -9.0066) (42.7983, -8.2526) knots 0 0 0 1 1 1
  spline S201 degree 2 poles (42.7983, -8.2526) (42.7983, -7.711) (42.4903, -7.3977) knots 0 0 0 1 1 1
  spline S202 degree 2 poles (42.4903, -7.3977) (42.1558, -7.0526) (41.5877, -7.0526) knots 0 0 0 1 1 1
  spline S203 degree 2 poles (41.5877, -7.0526) (40.993, -7.0526) (40.3718, -7.3552) knots 0 0 0 1 1 1
  spline S204 degree 2 poles (40.3718, -7.3552) (39.9629, -7.5623) (39.2514, -8.0561) knots 0 0 0 1 1 1
  spline S205 degree 2 poles (39.2514, -8.0561) (39.0709, -8.1942) (38.9859, -8.2897) knots 0 0 0 1 1 1
  spline S206 degree 2 poles (38.9859, -8.2897) (38.8903, -8.4172) (38.7523, -8.4172) knots 0 0 0 1 1 1
  spline S207 degree 2 poles (38.7523, -8.4172) (38.524, -8.4172) (38.2532, -8.0774) knots 0 0 0 1 1 1
  spline S208 degree 2 poles (38.2532, -8.0774) (38.0567, -7.8225) (38.0567, -7.6526) knots 0 0 0 1 1 1
  spline S209 degree 2 poles (38.0567, -7.6526) (38.0567, -7.488) (38.1311, -7.488) knots 0 0 0 1 1 1
  spline S210 degree 2 poles (38.1311, -7.488) (38.1735, -7.488) (38.2532, -7.5995) knots 0 0 0 1 1 1
  spline S211 degree 2 poles (38.2532, -7.5995) (38.4019, -7.8172) (38.5346, -7.8331) knots 0 0 0 1 1 1
  spline S212 degree 2 poles (38.5346, -7.8331) (38.5505, -7.8331) (38.5718, -7.8331) knots 0 0 0 1 1 1
  spline S213 degree 2 poles (38.5718, -7.8331) (38.6992, -7.8331) (38.8691, -7.7481) knots 0 0 0 1 1 1
  spline S214 degree 2 poles (38.8691, -7.7481) (40.1063, -7.1481) (40.2019, -7.1004) knots 0 0 0 1 1 1
  spline S215 degree 2 poles (40.2019, -7.1004) (40.9611, -6.7552) (41.5824, -6.7552) knots 0 0 0 1 1 1
  spline S216 degree 2 poles (51.5381, -4.7428) (51.7558, -4.7428) (52.0213, -4.8543) knots 0 0 0 1 1 1
  spline S217 degree 2 poles (52.0213, -4.8543) (52.2496, -4.934) (52.2496, -5.1039) knots 0 0 0 1 1 1
  spline S218 degree 2 poles (52.2496, -5.1039) (52.2496, -5.3216) (51.9735, -5.3322) knots 0 0 0 1 1 1
  spline S219 degree 2 poles (51.9735, -5.3322) (51.0231, -5.3641) (50.3275, -5.6136) knots 0 0 0 1 1 1
  spline S220 degree 2 poles (50.3275, -5.6136) (49.6266, -5.8632) (49.1063, -6.5641) knots 0 0 0 1 1 1
  spline S221 degree 2 poles (49.1063, -6.5641) (48.6284, -7.2172) (48.6284, -7.8862) knots 0 0 0 1 1 1
  spline S222 degree 2 poles (48.6284, -7.8862) (48.6284, -8.7995) (49.2019, -9.2561) knots 0 0 0 1 1 1
  spline S223 degree 2 poles (49.2019, -9.2561) (49.5045, -9.5163) (49.9558, -9.665) knots 0 0 0 1 1 1
  spline S224 degree 2 poles (49.9558, -9.665) (50.3222, -9.7765) (50.6673, -9.7818) knots 0 0 0 1 1 1
  spline S225 degree 2 poles (50.6673, -9.7818) (51.0815, -9.803) (51.3098, -9.9251) knots 0 0 0 1 1 1
  spline S226 degree 2 poles (51.3098, -9.9251) (51.5116, -10.0313) (51.5116, -10.2331) knots 0 0 0 1 1 1
  spline S227 degree 2 poles (51.5116, -10.2331) (51.5116, -10.4508) (51.124, -10.4508) knots 0 0 0 1 1 1
  spline S228 degree 2 poles (51.124, -10.4508) (50.5824, -10.4508) (49.9771, -10.2543) knots 0 0 0 1 1 1
  spline S229 degree 2 poles (49.9771, -10.2543) (49.3771, -10.0632) (49.016, -9.7499) knots 0 0 0 1 1 1
  spline S230 degree 2 poles (49.016, -9.7499) (48.278, -9.1393) (48.278, -8.1358) knots 0 0 0 1 1 1
  spline S231 degree 2 poles (48.278, -8.1358) (48.278, -7.2862) (48.7718, -6.5481) knots 0 0 0 1 1 1
  spline S232 degree 2 poles (48.7718, -6.5481) (49.1965, -5.911) (49.8762, -5.5287) knots 0 0 0 1 1 1
  line L29 (49.8762, -5.5287) -> (49.8603, -5.5074)
  spline S233 degree 2 poles (49.8603, -5.5074) (48.4957, -5.9057) (47.593, -6.2349) knots 0 0 0 1 1 1
  spline S234 degree 2 poles (47.593, -6.2349) (47.2426, -6.3623) (46.9665, -6.5163) knots 0 0 0 1 1 1
  spline S235 degree 2 poles (46.9665, -6.5163) (46.8284, -6.6119) (46.6797, -6.6119) knots 0 0 0 1 1 1
  spline S236 degree 2 poles (46.6797, -6.6119) (46.4196, -6.6119) (46.1222, -6.2667) knots 0 0 0 1 1 1
  spline S237 degree 2 poles (46.1222, -6.2667) (45.8939, -5.9747) (45.8939, -5.7835) knots 0 0 0 1 1 1
  spline S238 degree 2 poles (45.8939, -5.7835) (45.8939, -5.6243) (45.9788, -5.6243) knots 0 0 0 1 1 1
  spline S239 degree 2 poles (45.9788, -5.6243) (46.016, -5.6243) (46.0903, -5.6986) knots 0 0 0 1 1 1
  spline S240 degree 2 poles (46.0903, -5.6986) (46.2549, -5.8791) (46.3718, -5.9375) knots 0 0 0 1 1 1
  spline S241 degree 2 poles (46.3718, -5.9375) (46.4939, -5.9959) (46.6532, -5.9906) knots 0 0 0 1 1 1
  spline S242 degree 2 poles (46.6532, -5.9906) (46.8231, -5.9906) (47.1948, -5.9004) knots 0 0 0 1 1 1
  line L30 (47.1948, -5.9004) -> (50.8638, -4.9605)
  spline S243 degree 2 poles (50.8638, -4.9605) (51.1187, -4.9074) (51.2567, -4.8278) knots 0 0 0 1 1 1
  spline S244 degree 2 poles (51.2567, -4.8278) (51.3842, -4.7428) (51.5381, -4.7428) knots 0 0 0 1 1 1
  spline S245 degree 2 poles (57.7983, -5.6561) (57.9629, -6.2243) (58.2443, -6.8402) knots 0 0 0 1 1 1
  spline S246 degree 2 poles (58.2443, -6.8402) (58.7594, -6.6278) (59.0726, -6.4207) knots 0 0 0 1 1 1
  spline S247 degree 2 poles (59.0726, -6.4207) (59.1257, -6.3835) (59.1257, -6.357) knots 0 0 0 1 1 1
  spline S248 degree 2 poles (59.1257, -6.357) (59.1257, -6.3251) (59.0886, -6.2933) knots 0 0 0 1 1 1
  spline S249 degree 2 poles (59.0886, -6.2933) (58.9399, -6.134) (58.7541, -5.98) knots 0 0 0 1 1 1
  spline S250 degree 2 poles (58.7541, -5.98) (58.6691, -5.9163) (58.6691, -5.8685) knots 0 0 0 1 1 1
  spline S251 degree 2 poles (58.6691, -5.8685) (58.6691, -5.8101) (58.7434, -5.8101) knots 0 0 0 1 1 1
  spline S252 degree 2 poles (58.7434, -5.8101) (58.7859, -5.8101) (58.8709, -5.8526) knots 0 0 0 1 1 1
  spline S253 degree 2 poles (58.8709, -5.8526) (59.0036, -5.9269) (59.1948, -6.0012) knots 0 0 0 1 1 1
  spline S254 degree 2 poles (59.1948, -6.0012) (59.3541, -6.065) (59.439, -6.065) knots 0 0 0 1 1 1
  spline S255 degree 2 poles (59.439, -6.065) (59.4815, -6.065) (59.5558, -6.0543) knots 0 0 0 1 1 1
  spline S256 degree 2 poles (59.5558, -6.0543) (59.6408, -6.0437) (59.678, -6.0384) knots 0 0 0 1 1 1
  spline S257 degree 2 poles (59.678, -6.0384) (59.7735, -6.0331) (59.8585, -6.0862) knots 0 0 0 1 1 1
  spline S258 degree 2 poles (59.8585, -6.0862) (59.9275, -6.134) (59.9275, -6.1924) knots 0 0 0 1 1 1
  spline S259 degree 2 poles (59.9275, -6.1924) (59.9275, -6.3411) (59.7895, -6.4366) knots 0 0 0 1 1 1
  spline S260 degree 2 poles (59.7895, -6.4366) (59.1842, -6.872) (58.4036, -7.18) knots 0 0 0 1 1 1
  spline S261 degree 2 poles (58.4036, -7.18) (58.7169, -7.7906) (59.1842, -8.3959) knots 0 0 0 1 1 1
  spline S262 degree 2 poles (59.1842, -8.3959) (59.4284, -8.7145) (59.4284, -8.9694) knots 0 0 0 1 1 1
  spline S263 degree 2 poles (59.4284, -8.9694) (59.4284, -9.3251) (59.2266, -9.3251) knots 0 0 0 1 1 1
  spline S264 degree 2 poles (59.2266, -9.3251) (59.1098, -9.3251) (59.0408, -9.2402) knots 0 0 0 1 1 1
  spline S265 degree 2 poles (59.0408, -9.2402) (58.8178, -8.98) (58.4142, -8.8951) knots 0 0 0 1 1 1
  spline S266 degree 2 poles (58.4142, -8.8951) (57.7452, -8.7517) (57.2196, -8.7517) knots 0 0 0 1 1 1
  spline S267 degree 2 poles (57.2196, -8.7517) (56.6514, -8.7517) (56.2797, -8.9269) knots 0 0 0 1 1 1
  spline S268 degree 2 poles (56.2797, -8.9269) (55.8337, -9.1287) (55.8337, -9.5535) knots 0 0 0 1 1 1
  spline S269 degree 2 poles (55.8337, -9.5535) (55.8337, -10.0844) (56.6302, -10.2968) knots 0 0 0 1 1 1
  spline S270 degree 2 poles (56.6302, -10.2968) (57.0762, -10.4136) (57.6868, -10.4136) knots 0 0 0 1 1 1
  line L31 (57.6868, -10.4136) -> (58.2549, -10.3871)
  spline S271 degree 2 poles (58.2549, -10.3871) (58.685, -10.3871) (58.685, -10.6738) knots 0 0 0 1 1 1
  spline S272 degree 2 poles (58.685, -10.6738) (58.685, -10.8597) (58.5151, -10.9128) knots 0 0 0 1 1 1
  spline S273 degree 2 poles (58.5151, -10.9128) (58.3665, -10.9605) (57.9629, -10.9605) knots 0 0 0 1 1 1
  spline S274 degree 2 poles (57.9629, -10.9605) (56.9806, -10.9605) (56.2903, -10.6366) knots 0 0 0 1 1 1
  spline S275 degree 2 poles (56.2903, -10.6366) (55.5098, -10.2703) (55.5098, -9.6012) knots 0 0 0 1 1 1
  spline S276 degree 2 poles (55.5098, -9.6012) (55.5098, -8.9481) (56.2319, -8.6508) knots 0 0 0 1 1 1
  spline S277 degree 2 poles (56.2319, -8.6508) (56.7257, -8.449) (57.4638, -8.449) knots 0 0 0 1 1 1
  spline S278 degree 2 poles (57.4638, -8.449) (58.2178, -8.449) (58.77, -8.5393) knots 0 0 0 1 1 1
  spline S279 degree 2 poles (58.77, -8.5393) (58.462, -8.0402) (58.1063, -7.2968) knots 0 0 0 1 1 1
  spline S280 degree 2 poles (58.1063, -7.2968) (57.2461, -7.5995) (56.5505, -7.5995) knots 0 0 0 1 1 1
  spline S281 degree 2 poles (56.5505, -7.5995) (55.7541, -7.5995) (55.7541, -7.0579) knots 0 0 0 1 1 1
  spline S282 degree 2 poles (55.7541, -7.0579) (55.7541, -6.872) (55.8709, -6.665) knots 0 0 0 1 1 1
  spline S283 degree 2 poles (55.8709, -6.665) (55.9293, -6.5588) (55.9824, -6.5588) knots 0 0 0 1 1 1
  spline S284 degree 2 poles (55.9824, -6.5588) (56.078, -6.5588) (56.078, -6.6278) knots 0 0 0 1 1 1
  spline S285 degree 2 poles (56.078, -6.6278) (56.078, -6.665) (56.0514, -6.7393) knots 0 0 0 1 1 1
  spline S286 degree 2 poles (56.0514, -6.7393) (56.0249, -6.8402) (56.0249, -6.9782) knots 0 0 0 1 1 1
  spline S287 degree 2 poles (56.0249, -6.9782) (56.0249, -7.2278) (56.4549, -7.2278) knots 0 0 0 1 1 1
  spline S288 degree 2 poles (56.4549, -7.2278) (57.1134, -7.2278) (57.9364, -6.9517) knots 0 0 0 1 1 1
  spline S289 degree 2 poles (57.9364, -6.9517) (57.862, -6.7765) (57.485, -5.7676) knots 0 0 0 1 1 1
  spline S290 degree 2 poles (57.485, -5.7676) (56.5771, -6.0703) (56.0408, -6.0703) knots 0 0 0 1 1 1
  spline S291 degree 2 poles (56.0408, -6.0703) (55.4461, -6.0703) (55.085, -5.7464) knots 0 0 0 1 1 1
  spline S292 degree 2 poles (55.085, -5.7464) (55.0213, -5.6827) (55.0213, -5.6189) knots 0 0 0 1 1 1
  spline S293 degree 2 poles (55.0213, -5.6189) (55.0213, -5.5287) (55.0957, -5.5287) knots 0 0 0 1 1 1
  spline S294 degree 2 poles (55.0957, -5.5287) (55.1222, -5.5287) (55.2072, -5.5605) knots 0 0 0 1 1 1
  spline S295 degree 2 poles (55.2072, -5.5605) (55.5311, -5.7145) (55.8921, -5.7145) knots 0 0 0 1 1 1
  spline S296 degree 2 poles (55.8921, -5.7145) (56.4815, -5.7145) (57.3682, -5.3959) knots 0 0 0 1 1 1
  spline S297 degree 2 poles (57.3682, -5.3959) (57.3151, -5.2313) (57.2142, -4.934) knots 0 0 0 1 1 1
  spline S298 degree 2 poles (57.2142, -4.934) (57.1187, -4.6526) (57.0762, -4.5145) knots 0 0 0 1 1 1
  spline S299 degree 2 poles (57.0762, -4.5145) (56.9647, -4.2066) (56.5771, -4.2066) knots 0 0 0 1 1 1
  spline S300 degree 2 poles (56.5771, -4.2066) (56.5134, -4.2066) (56.4815, -4.2066) knots 0 0 0 1 1 1
  spline S301 degree 2 poles (56.4815, -4.2066) (56.4657, -4.2066) (56.4656, -4.2066) knots 0 0 0 1 1 1
  spline S302 degree 2 poles (56.4656, -4.2066) (56.3912, -4.2066) (56.3912, -4.1322) knots 0 0 0 1 1 1
  spline S303 degree 2 poles (56.3912, -4.1322) (56.3912, -4.0791) (56.4549, -4.026) knots 0 0 0 1 1 1
  spline S304 degree 2 poles (56.4549, -4.026) (56.593, -3.9198) (56.7576, -3.9198) knots 0 0 0 1 1 1
  spline S305 degree 2 poles (56.7576, -3.9198) (57.0974, -3.9198) (57.3895, -4.0313) knots 0 0 0 1 1 1
  spline S306 degree 2 poles (57.3895, -4.0313) (57.6496, -4.1269) (57.6496, -4.2597) knots 0 0 0 1 1 1
  spline S307 degree 2 poles (57.6496, -4.2597) (57.6496, -4.3287) (57.6019, -4.4455) knots 0 0 0 1 1 1
  spline S308 degree 2 poles (57.6019, -4.4455) (57.5806, -4.4986) (57.5806, -4.557) knots 0 0 0 1 1 1
  spline S309 degree 2 poles (57.5806, -4.557) (57.5806, -4.6154) (57.6125, -4.8012) knots 0 0 0 1 1 1
  spline S310 degree 2 poles (57.6125, -4.8012) (57.6549, -5.0774) (57.6974, -5.2685) knots 0 0 0 1 1 1
  spline S311 degree 2 poles (57.6974, -5.2685) (58.0001, -5.157) (58.2443, -5.0243) knots 0 0 0 1 1 1
  spline S312 degree 2 poles (58.2443, -5.0243) (58.4249, -4.9287) (58.4939, -4.8756) knots 0 0 0 1 1 1
  spline S313 degree 2 poles (58.4939, -4.8756) (58.6107, -4.7641) (58.7965, -4.6951) knots 0 0 0 1 1 1
  spline S314 degree 2 poles (58.7965, -4.6951) (58.9399, -4.6366) (59.0355, -4.6366) knots 0 0 0 1 1 1
  spline S315 degree 2 poles (59.0355, -4.6366) (59.1364, -4.6366) (59.2001, -4.7057) knots 0 0 0 1 1 1
  spline S316 degree 2 poles (59.2001, -4.7057) (59.2532, -4.7641) (59.2532, -4.8384) knots 0 0 0 1 1 1
  spline S317 degree 2 poles (59.2532, -4.8384) (59.2532, -5.0083) (59.1151, -5.0774) knots 0 0 0 1 1 1
  spline S318 degree 2 poles (59.1151, -5.0774) (58.5417, -5.3906) (57.7983, -5.6561) knots 0 0 0 1 1 1
  spline S319 degree 2 poles (65.4178, -5.7835) (65.8585, -5.6402) (66.2726, -5.4437) knots 0 0 0 1 1 1
  spline S320 degree 2 poles (66.2726, -5.4437) (66.5594, -5.311) (66.6815, -5.311) knots 0 0 0 1 1 1
  spline S321 degree 2 poles (66.6815, -5.311) (66.7877, -5.311) (66.862, -5.3694) knots 0 0 0 1 1 1
  spline S322 degree 2 poles (66.862, -5.3694) (66.9417, -5.4278) (66.9417, -5.5181) knots 0 0 0 1 1 1
  spline S323 degree 2 poles (66.9417, -5.5181) (66.9417, -5.6933) (66.6443, -5.8101) knots 0 0 0 1 1 1
  spline S324 degree 2 poles (66.6443, -5.8101) (65.9859, -6.0543) (65.2638, -6.2508) knots 0 0 0 1 1 1
  spline S325 degree 2 poles (65.2638, -6.2508) (64.17, -9.3092) (63.6974, -10.3924) knots 0 0 0 1 1 1
  spline S326 degree 2 poles (63.6974, -10.3924) (63.6019, -10.6048) (63.4266, -10.6048) knots 0 0 0 1 1 1
  spline S327 degree 2 poles (63.4266, -10.6048) (63.3045, -10.6048) (63.2302, -10.5198) knots 0 0 0 1 1 1
  spline S328 degree 2 poles (63.2302, -10.5198) (63.1718, -10.4349) (63.1718, -10.3287) knots 0 0 0 1 1 1
  spline S329 degree 2 poles (63.1718, -10.3287) (63.1718, -10.2597) (63.2142, -10.1588) knots 0 0 0 1 1 1
  spline S330 degree 2 poles (63.2142, -10.1588) (64.085, -8.4384) (64.839, -6.357) knots 0 0 0 1 1 1
  spline S331 degree 2 poles (64.839, -6.357) (64.3027, -6.4844) (63.9311, -6.4844) knots 0 0 0 1 1 1
  spline S332 degree 2 poles (63.9311, -6.4844) (63.4319, -6.4844) (63.1134, -6.2508) knots 0 0 0 1 1 1
  spline S333 degree 2 poles (63.1134, -6.2508) (62.8691, -6.0756) (62.8691, -5.9375) knots 0 0 0 1 1 1
  spline S334 degree 2 poles (62.8691, -5.9375) (62.8691, -5.842) (62.9647, -5.842) knots 0 0 0 1 1 1
  spline S335 degree 2 poles (62.9647, -5.842) (63.0019, -5.842) (63.1187, -5.9216) knots 0 0 0 1 1 1
  spline S336 degree 2 poles (63.1187, -5.9216) (63.4107, -6.1128) (63.8408, -6.1128) knots 0 0 0 1 1 1
  spline S337 degree 2 poles (63.8408, -6.1128) (64.2815, -6.1128) (64.9877, -5.8951) knots 0 0 0 1 1 1
  spline S338 degree 2 poles (64.9877, -5.8951) (65.1364, -5.4756) (65.2266, -5.1411) knots 0 0 0 1 1 1
  spline S339 degree 2 poles (65.2266, -5.1411) (65.3116, -4.8437) (65.3116, -4.7004) knots 0 0 0 1 1 1
  spline S340 degree 2 poles (65.3116, -4.7004) (65.3116, -4.4083) (64.908, -4.3181) knots 0 0 0 1 1 1
  spline S341 degree 2 poles (64.908, -4.3181) (64.7647, -4.2915) (64.7647, -4.2384) knots 0 0 0 1 1 1
  spline S342 degree 2 poles (64.7647, -4.2384) (64.7647, -4.18) (64.8815, -4.1269) knots 0 0 0 1 1 1
  spline S343 degree 2 poles (64.8815, -4.1269) (65.0249, -4.0844) (65.1098, -4.0844) knots 0 0 0 1 1 1
  spline S344 degree 2 poles (65.1098, -4.0844) (65.2373, -4.0844) (65.4656, -4.1747) knots 0 0 0 1 1 1
  spline S345 degree 2 poles (65.4656, -4.1747) (65.6833, -4.2597) (65.816, -4.3712) knots 0 0 0 1 1 1
  spline S346 degree 2 poles (65.816, -4.3712) (65.9647, -4.488) (65.9647, -4.6154) knots 0 0 0 1 1 1
  spline S347 degree 2 poles (65.9647, -4.6154) (65.9647, -4.7641) (65.8426, -4.8543) knots 0 0 0 1 1 1
  spline S348 degree 2 poles (65.8426, -4.8543) (65.7629, -4.9181) (65.6673, -5.1411) knots 0 0 0 1 1 1
  spline S349 degree 2 poles (65.6673, -5.1411) (65.6196, -5.2366) (65.4178, -5.7835) knots 0 0 0 1 1 1
  spline S350 degree 2 poles (66.1187, -8.9057) (66.0656, -9.0915) (66.0656, -9.3145) knots 0 0 0 1 1 1
  spline S351 degree 2 poles (66.0656, -9.3145) (66.0656, -9.7871) (66.4957, -10.0101) knots 0 0 0 1 1 1
  spline S352 degree 2 poles (66.4957, -10.0101) (66.8355, -10.1853) (67.6213, -10.1853) knots 0 0 0 1 1 1
  spline S353 degree 2 poles (67.6213, -10.1853) (68.0355, -10.1853) (68.3965, -10.1057) knots 0 0 0 1 1 1
  spline S354 degree 2 poles (68.3965, -10.1057) (68.5824, -10.0526) (68.7417, -10.0526) knots 0 0 0 1 1 1
  spline S355 degree 2 poles (68.7417, -10.0526) (68.8744, -10.0526) (69.0019, -10.1057) knots 0 0 0 1 1 1
  spline S356 degree 2 poles (69.0019, -10.1057) (69.1718, -10.1747) (69.1718, -10.3393) knots 0 0 0 1 1 1
  spline S357 degree 2 poles (69.1718, -10.3393) (69.1718, -10.4667) (69.0921, -10.5251) knots 0 0 0 1 1 1
  spline S358 degree 2 poles (69.0921, -10.5251) (69.0125, -10.5835) (68.8107, -10.6101) knots 0 0 0 1 1 1
  spline S359 degree 2 poles (68.8107, -10.6101) (68.4072, -10.6685) (67.8868, -10.6685) knots 0 0 0 1 1 1
  spline S360 degree 2 poles (67.8868, -10.6685) (66.8355, -10.6685) (66.3257, -10.3552) knots 0 0 0 1 1 1
  spline S361 degree 2 poles (66.3257, -10.3552) (66.0709, -10.1959) (65.9275, -9.9358) knots 0 0 0 1 1 1
  spline S362 degree 2 poles (65.9275, -9.9358) (65.7948, -9.7074) (65.7948, -9.4685) knots 0 0 0 1 1 1
  spline S363 degree 2 poles (65.7948, -9.4685) (65.7948, -9.1818) (65.9488, -8.8473) knots 0 0 0 1 1 1
  spline S364 degree 2 poles (65.9488, -8.8473) (66.0125, -8.6933) (66.0974, -8.6933) knots 0 0 0 1 1 1
  spline S365 degree 2 poles (66.0974, -8.6933) (66.1558, -8.6933) (66.1558, -8.757) knots 0 0 0 1 1 1
  spline S366 degree 2 poles (66.1558, -8.757) (66.1558, -8.7729) (66.1187, -8.9057) knots 0 0 0 1 1 1
  spline S367 degree 2 poles (67.7381, -7.0526) (67.7859, -7.0101) (67.7859, -6.9889) knots 0 0 0 1 1 1
  spline S368 degree 2 poles (67.7859, -6.9889) (67.7859, -6.9729) (67.7275, -6.9676) knots 0 0 0 1 1 1
  spline S369 degree 2 poles (67.7275, -6.9676) (67.6691, -6.9623) (67.5948, -6.9623) knots 0 0 0 1 1 1
  spline S370 degree 2 poles (67.5948, -6.9623) (66.793, -6.9623) (66.2461, -7.2543) knots 0 0 0 1 1 1
  spline S371 degree 2 poles (66.2461, -7.2543) (66.1983, -7.2756) (66.1558, -7.2756) knots 0 0 0 1 1 1
  spline S372 degree 2 poles (66.1558, -7.2756) (66.0868, -7.2756) (66.0868, -7.2172) knots 0 0 0 1 1 1
  spline S373 degree 2 poles (66.0868, -7.2172) (66.0868, -7.1535) (66.1505, -7.1004) knots 0 0 0 1 1 1
  spline S374 degree 2 poles (66.1505, -7.1004) (66.8142, -6.6066) (67.7488, -6.6066) knots 0 0 0 1 1 1
  spline S375 degree 2 poles (67.7488, -6.6066) (67.8125, -6.6066) (67.8921, -6.6119) knots 0 0 0 1 1 1
  spline S376 degree 2 poles (67.8921, -6.6119) (68.4019, -6.6384) (68.6886, -6.7765) knots 0 0 0 1 1 1
  spline S377 degree 2 poles (68.6886, -6.7765) (68.9381, -6.8986) (68.9222, -7.0844) knots 0 0 0 1 1 1
  spline S378 degree 2 poles (68.9222, -7.0844) (68.9116, -7.2809) (68.7204, -7.265) knots 0 0 0 1 1 1
  spline S379 degree 2 poles (68.7204, -7.265) (68.6461, -7.265) (68.5346, -7.2225) knots 0 0 0 1 1 1
  spline S380 degree 2 poles (68.5346, -7.2225) (68.3806, -7.1747) (68.3116, -7.1747) knots 0 0 0 1 1 1
  spline S381 degree 2 poles (68.3116, -7.1747) (68.2903, -7.1747) (68.2691, -7.1747) knots 0 0 0 1 1 1
  spline S382 degree 2 poles (68.2691, -7.1747) (68.147, -7.1747) (67.9824, -7.249) knots 0 0 0 1 1 1
  spline S383 degree 2 poles (67.9824, -7.249) (67.8284, -7.3181) (67.1275, -7.7906) knots 0 0 0 1 1 1
  spline S384 degree 2 poles (67.1275, -7.7906) (67.0532, -7.8331) (66.9895, -7.8331) knots 0 0 0 1 1 1
  spline S385 degree 2 poles (66.9895, -7.8331) (66.9311, -7.8331) (66.9311, -7.7641) knots 0 0 0 1 1 1
  spline S386 degree 2 poles (66.9311, -7.7641) (66.9311, -7.7269) (67.0107, -7.6579) knots 0 0 0 1 1 1